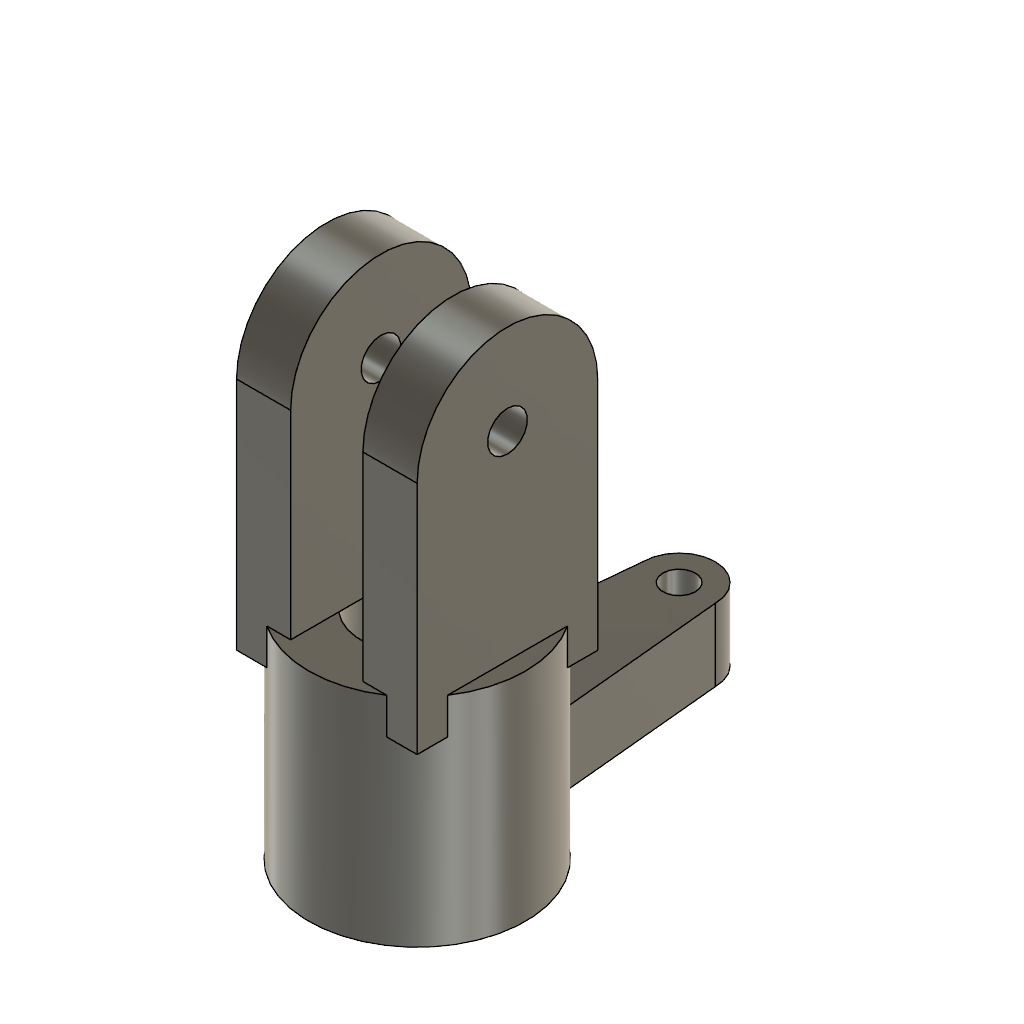
grip-r2-fit-only (Autodesk Fusion 360 design; units mm, degrees)
part number: 2026-11-01-14-40-38-236
Autodesk Fusion 360 part; units mm, degrees
ref_plane "WorkPlane1" through (0, 0, 0) normal (0, 0, 1) x (1, 0, 0)
sketch "Bearing housing OD12 assumed" plane through (0, 0, 0) normal (0, 0, 1) x (1, 0, 0)
  circle A0 centre (0, 0) radius 6
extrude "Bearing housing OD12 assumed (1)" add sketch "Bearing housing OD12 assumed" along normal blind 12
ref_plane "WorkPlane2" through (-5, 0, 0) normal (1, 0, 0) x (0, 1, 0)
sketch "Rounded cheek A - 4 mm gap assumed" plane through (-5, 0, 0) normal (1, 0, 0) x (0, 0, -1)
  line L0 (-10, -5) -> (-10, 5)
  line L1 (-10, 5) -> (-23, 5)
  arc A0 (-23, 5) -> (-23, -5) centre (-23, 0) ccw
  line L2 (-23, -5) -> (-10, -5)
extrude "Rounded cheek A - 4 mm gap assumed (1)" add sketch "Rounded cheek A - 4 mm gap assumed" along normal blind 3
ref_plane "WorkPlane3" through (2, 0, 0) normal (1, 0, 0) x (0, 1, 0)
sketch "Rounded cheek B - 3 mm wall assumed" plane through (2, 0, 0) normal (1, 0, 0) x (0, 0, -1)
  line L0 (-10, -5) -> (-10, 5)
  line L1 (-10, 5) -> (-23, 5)
  arc A0 (-23, 5) -> (-23, -5) centre (-23, 0) ccw
  line L2 (-23, -5) -> (-10, -5)
extrude "Rounded cheek B - 3 mm wall assumed (1)" add sketch "Rounded cheek B - 3 mm wall assumed" along normal blind 3
ref_plane "WorkPlane4" through (0, 0, 2) normal (0, 0, 1) x (1, 0, 0)
sketch "Rounded pitch arm - geometry assumed" plane through (0, 0, 2) normal (0, 0, 1) x (1, 0, 0)
  line L0 (-3, 4) -> (3, 4)
  line L1 (3, 4) -> (2, 14.5)
  arc A0 (2, 14.5) -> (-2, 14.5) centre (0, 14.5) ccw
  line L2 (-2, 14.5) -> (-3, 4)
extrude "Rounded pitch arm - geometry assumed (1)" add sketch "Rounded pitch arm - geometry assumed" along normal blind 4
ref_plane "WorkPlane5" through (0, 0, 0) normal (0, 0, 1) x (1, 0, 0)
sketch "Internal shoulder relief assumed" plane through (0, 0, 0) normal (0, 0, 1) x (1, 0, 0)
  circle A0 centre (0, 0) radius 2.4
extrude "Internal shoulder relief assumed (1)" cut sketch "Internal shoulder relief assumed" along normal blind 12
ref_plane "WorkPlane6" through (0, 0, 0) normal (0, 0, 1) x (1, 0, 0)
sketch "Inner radial pocket 6.15 assumed allowance" plane through (0, 0, 0) normal (0, 0, 1) x (1, 0, 0)
  circle A0 centre (0, 0) radius 3.075
extrude "Inner radial pocket 6.15 assumed allowance (1)" cut sketch "Inner radial pocket 6.15 assumed allowance" along normal blind 2.5
ref_plane "WorkPlane7" through (0, 0, 3.9) normal (0, 0, 1) x (1, 0, 0)
sketch "Outer radial and thrust access pocket" plane through (0, 0, 3.9) normal (0, 0, 1) x (1, 0, 0)
  circle A0 centre (0, 0) radius 3.075
extrude "Outer radial and thrust access pocket (1)" cut sketch "Outer radial and thrust access pocket" along normal blind 8.1
sketch "Blade bolt 2.2 mm assumed" plane through (0, 0, 0) normal (1, 0, 0) x (0, 0, -1)
  circle A0 centre (-23, 0) radius 1.1
extrude "Extrude8" cut sketch "Blade bolt 2.2 mm assumed" along normal mid plane 40
ref_plane "WorkPlane8" through (0, 0, 2) normal (0, 0, 1) x (1, 0, 0)
sketch "Pitch ball mounting 1.8 mm assumed" plane through (0, 0, 2) normal (0, 0, 1) x (1, 0, 0)
  circle A0 centre (0, 14.5) radius 0.9
extrude "Extrude9" cut sketch "Pitch ball mounting 1.8 mm assumed" along normal blind 4
named bodies: "PETG grip - fit prototype only"
